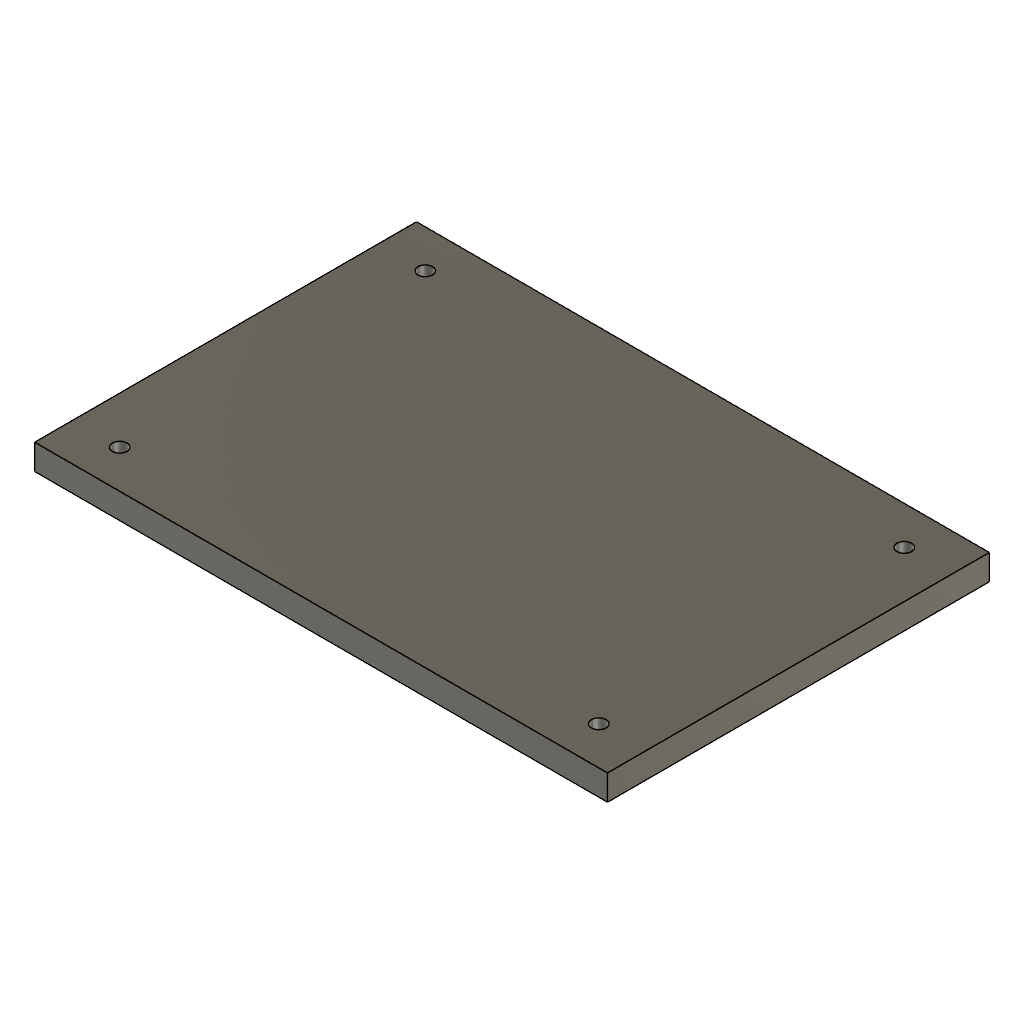
02-25 Humidifier chamber top lid v2 (Autodesk Fusion 360 design; units mm, degrees)
Autodesk Fusion 360 part; units mm, degrees
sketch "Sketch1" plane through (0, 0, 0) normal (0, 0, 1) x (1, 0, 0)
  line L0 (0, 0) -> (90, 0)
  line L1 (90, 0) -> (90, 60)
  line L2 (90, 60) -> (0, 60)
  line L3 (0, 60) -> (0, 0)
  circle A0 centre (82.625, 6) radius 1.15
  circle A1 centre (7.375, 6) radius 1.15
  circle A2 centre (7.375, 54) radius 1.15
  circle A3 centre (82.625, 54) radius 1.15
  dimension "d1" = 60
  dimension "d2" = 90
  dimension "d3" = 2.3
  dimension "d4" = 6
  dimension "d5" = 7.375
  dimension "d6" = 6
  dimension "d7" = 7.375
  constraint horizontal L0
  constraint vertical L1
  constraint horizontal L2
  constraint vertical L3
  constraint coincident L0.start L3.end
  constraint equal A0 A1
  constraint equal A1 A2
  constraint equal A2 A3
  constraint horizontal A0.centre A1.centre
  constraint vertical A0.centre A3.centre
  constraint vertical A1.centre A2.centre
  constraint horizontal A2.centre A3.centre
  measures "d1" distance of L0.end L1.end
  measures "d2" distance of L1.end L2.end
  measures "d3" diameter of A0
  measures "d4" distance of L0 A0.centre
  measures "d5" distance of L1 A0.centre
  measures "d6" distance of L2 A3.centre
  measures "d7" distance of L3 A1.centre
extrude "Extrude1" add sketch "Sketch1" along normal blind 4
